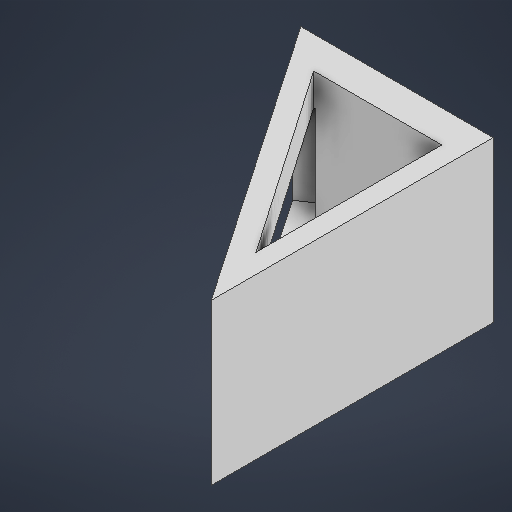
# Autodesk Inventor part: lampe
Saved by Autodesk Inventor 2026 (Build 300175000, 175)
## iProperties
Created: 2026-10-28
Part Number: lampe
Material: Generic
Document SubType Name: Modeling
Designer: alexp
Density: 1 g/cm^3
Appearance: Default
Author: alexp
Autodesk Inventor part; units mm, degrees
ref_plane "YZ Plane" through (0, 0, 0) normal (1, 0, 0) x (0, 1, 0)
ref_plane "XZ Plane" through (0, 0, 0) normal (0, 1, 0) x (-1, 0, 0)
ref_plane "XY Plane" through (0, 0, 0) normal (0, 0, 1) x (1, 0, 0)
sketch "Sketch3" plane through (0, 0, 0) normal (0, 1, 0) x (-1, 0, 0)
  line L0 (1.6659, 69.2703) -> (1.6659, 25.2703)
  line L1 (1.6659, 25.2703) -> (31.6659, 25.2703)
  line L2 (31.6659, 25.2703) -> (1.6659, 69.2703)
  line L3 (1.6659, 69.2703) -> (4.6659, 69.2703)
  line L4 (4.6659, 69.2703) -> (4.6659, 59.2703)
  line L5 (4.6659, 59.2703) -> (1.6659, 59.2703)
  line L6 (1.6659, 59.2703) -> (1.6659, 69.2703)
  line L7 (1.6659, 25.2703) -> (4.6659, 25.2703)
  line L8 (4.6659, 25.2703) -> (4.6659, 30.2703)
  line L9 (4.6659, 30.2703) -> (1.6659, 30.2703)
  line L10 (1.6659, 30.2703) -> (1.6659, 25.2703)
  line L11 (4.6659, 59.2703) -> (4.6659, 30.2703)
  line L12 (24.6659, 30.2703) -> (4.6659, 59.2703)
  line L13 (4.6659, 30.2703) -> (24.6659, 30.2703)
  line L14 (1.6659, 69.2703) -> (31.6659, 25.2703)
  point P0 (3.1659, 25.2703)
  point P1 (3.1659, 30.2703)
  dimension "d11" = 10
  dimension "d12" = 5
  dimension "d13" = 44
  dimension "d14" = 30
  dimension "d15" = 3
  dimension "d16" = 1.1135
  dimension "d17" = 20
  dimension "d18" = 29
  constraints: 30 end point, 4 parallel, 4 perpendicular, 2 horizontal, 2 midpoint, 1 collinear, 1 point on line, 1 vertical
  measures "d11" distance of L3.end L4.end
  measures "d12" distance of point (3.166, 25.27) point (3.166, 30.27)
  measures "d13" distance of L0.start L0.end
  measures "d14" distance of L0.end L1.end
  measures "d15" distance between parallel lines of L4 L0
  measures "d17" distance of L8.end L12.start
  measures "d18" distance of L4.end L8.end
extrude "Extrusion1" add sketch "Sketch3" along normal blind 25 contours L2 L4 L5 L0 | L5 L11 L9 L0 | L2 L1 L8 L13 L12 L4 | L9 L8 L1 L0
sketch "Sketch4" plane through (-1.6659, 0, 69.2703) normal (-0.8262273, 0, 0.5633368) x (0.5633368, 0, 0.8262273)
  line L0 (-53.2541, 25) -> (0, 25) projected
  line L1 (-53.2541, 0) -> (0, 0) projected
  line L2 (-48.2541, 5) -> (-5.2541, 5)
  line L3 (-5.2541, 5) -> (-5.2541, 20)
  line L4 (-5.2541, 20) -> (-48.2541, 20)
  line L5 (-48.2541, 20) -> (-48.2541, 5)
  line L6 (-53.2541, 0) -> (-53.2541, 25) projected
  point P0 (-56.2946, 0)
  point P1 (-5.2541, 12.5)
  dimension "d21" = 25
  dimension "d22" = 5
  dimension "d23" = 43
  dimension "d24" = 5
  dimension "d25" = 5
  constraints: 8 end point, 2 parallel, 1 horizontal, 1 midpoint, 1 perpendicular
  measures "d21" distance between parallel lines of L0 L1
  measures "d22" distance between parallel lines of L6 L5
  measures "d23" distance from line of point (-5.254, 12.5) L5
  measures "d24" distance between parallel lines of L0 L4
  measures "d25" distance between parallel lines of L1 L2
extrude "Extrusion2" cut sketch "Sketch4" against normal blind 3.2
sketch "Sketch7" plane through (-28.8492, 20, 29.4014) normal (0, -1, 0) x (0.8262273, 0, -0.5633368)
  line L0 (19.4915, 14.3412) -> (3.1547, 38.3018) projected
  line L1 (0, 43) -> (3.2, 43) projected
  line L2 (3.1547, 38.3018) -> (0, 43)
  line L3 (0, 43) -> (3.2, 43)
  line L4 (3.2, 43) -> (3.1547, 38.3018)
  line L5 (0, 43) -> (3.2, 43)
  point P0 (40.3989, -8.0404)
  constraints: 8 end point, 1 collinear
extrude "Extrusion3" add sketch "Sketch7" along normal blind 15
body "Solid1"
